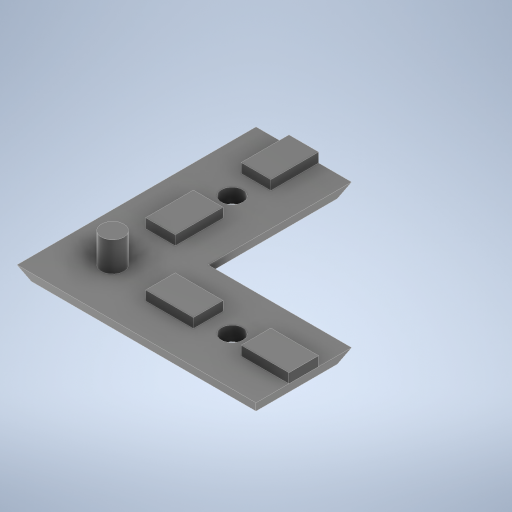
# Autodesk Inventor part: Angular_90grados
Saved by Autodesk Inventor 2024.3 (Build 283343010, 343A)
## iProperties
Created: 2025-08-07
Part Number: Angular_90grados
Material: Generic
Document SubType Name: Modeling
Designer: usuario
Density: 1 g/cm^3
Appearance: Smooth - Black
Author: usuario
Autodesk Inventor part; units mm, degrees
ref_plane "YZ Plane" through (0, 0, 0) normal (1, 0, 0) x (0, 1, 0)
ref_plane "XZ Plane" through (0, 0, 0) normal (0, 1, 0) x (-1, 0, 0)
ref_plane "XY Plane" through (0, 0, 0) normal (0, 0, 1) x (1, 0, 0)
sketch "Sketch1" plane through (0, 0, 0) normal (0, 1, 0) x (-1, 0, 0)
  line L0 (0, 0) -> (-50, 0)
  line L1 (-50, 0) -> (-50, -20)
  line L2 (-50, -20) -> (-20, -20)
  line L3 (-20, -20) -> (-20, -50)
  line L4 (-20, -50) -> (0, -50)
  line L5 (0, -50) -> (0, 0)
  dimension "d0" = 50
  dimension "d1" = 20
  dimension "d2" = 30
  dimension "d3" = 30
  constraints: 12 end point, 4 perpendicular, 1 horizontal, 1 vertical
  measures "d0" distance of L0.start L0.end
  measures "d1" distance of L0.end L1.end
  measures "d2" distance of L1.end L2.end
  measures "d3" distance of L2.end L3.end
extrude "Extrusion1" add sketch "Sketch1" along normal blind 3
sketch "Sketch2" plane through (0, 3, 0) normal (0, 1, 0) x (1, 0, 0)
  line L0 (20, 50) -> (0, 50) projected
  line L1 (6.9, 50) -> (13.1, 50)
  line L2 (13.1, 50) -> (13.1, 20)
  line L3 (13.1, 20) -> (6.9, 20)
  line L4 (6.9, 20) -> (6.9, 50)
  line L5 (20, 20) -> (20, 50) projected
  line L6 (6.9, 40) -> (13.1, 40)
  line L7 (6.9, 30) -> (13.1, 30)
  line L8 (20, 6.9) -> (50, 6.9)
  line L9 (50, 6.9) -> (50, 13.1)
  line L10 (50, 13.1) -> (20, 13.1)
  line L11 (20, 13.1) -> (20, 6.9)
  line L12 (50, 0) -> (50, 20) projected
  line L13 (30, 6.9) -> (30, 13.1)
  line L14 (40, 6.9) -> (40, 13.1)
  circle A0 centre (10, 10) radius 2.375
  point P0 (0, 0)
  point P1 (10, 50)
  point P2 (10, 50)
  point P3 (10, 20)
  point P4 (50, 10)
  point P5 (50, 10)
  point P6 (20, 10)
  dimension "d6" = 6.2
  dimension "d7" = 10
  dimension "d8" = 10
  dimension "d9" = 30
  dimension "d10" = 6.2
  dimension "d11" = 10
  dimension "d12" = 10
  dimension "d15" = 4.75
  constraints: 24 end point, 9 point on line, 6 midpoint, 5 perpendicular, 4 parallel, 3 horizontal, 2 coincident, 2 horizontal alignment, 2 vertical alignment, 1 centre point
  measures "d6" distance of L2.end L3.end
  measures "d7" distance from line of point (10, 20) L7
  measures "d8" distance between parallel lines of L0 L6
  measures "d9" distance of L10.end L9.end
  measures "d10" distance of L10.end L8.start
  measures "d11" distance between parallel lines of L9 L14
  measures "d12" distance between parallel lines of L11 L13
  measures "d15" diameter of A0
extrude "Extrusion2" add sketch "Sketch2" along normal blind 2 contours L2 L6 L4 L0 | L2 L3 L4 L7 | L11 L10 L13 L8 | L14 L10 L9 L8
extrude "Extrusion3" add sketch "Sketch2" along normal blind 6.2 contours A0
sketch "Sketch3" plane through (0, 3, 0) normal (0, 1, 0) x (1, 0, 0)
  line L0 (20, 20) -> (20, 50) projected
  line L1 (20, 50) -> (13.1, 50) projected
  point P0 (0, 0)
  point P1 (10, 35)
  dimension "d18" = 10
  dimension "d26" = 15
  measures "d18" distance from line of L0 point (10, 35)
  measures "d26" distance from line of L1 point (10, 35)
hole "Hole1" at (10, 3, -35) direction (0, -1, 0) diameter 4.5 end through all
sketch "Sketch4" plane through (0, 3, 0) normal (0, 1, 0) x (1, 0, 0)
  line L0 (0, 0) -> (50, 0) projected
  line L1 (50, 0) -> (50, 6.9) projected
  point P0 (35, 10)
  dimension "d27" = 10
  dimension "d35" = 15
  measures "d27" distance from line of L0 point (35, 10)
  measures "d35" distance from line of L1 point (35, 10)
hole "Hole2" at (35, 3, -10) direction (0, -1, 0) diameter 4.5 end through all
chamfer "Chamfer1" distance 3 distance2 1.5 1 edges at (0, 0, -25) measured on face at (0, 1, -33.3333)
chamfer "Chamfer2" distance 3 distance2 1.5 1 edges at (10.7498, 0, -50) measured on face at (11.5332, 1, -50)
chamfer "Chamfer3" distance 3 distance2 1.5 1 edges at (20, 0, -34.25) measured on face at (20, 2, -39.5)
chamfer "Chamfer4" distance 3 distance2 1.5 1 edges at (35, 0, -20) measured on face at (40, 1.9998, -20)
chamfer "Chamfer5" distance 3 distance2 1.5 1 edges at (25.7498, 0, 0) measured on face at (17.1665, 2, 0)
chamfer "Chamfer6" distance 3 distance2 1.5 1 edges at (50, 0, -10) measured on face at (50, 1, -8.9667)
equation "\"d8\" = d7"
equation "\"d11\" = d7"
equation "\"d12\" = d7"
body "Solid1"
